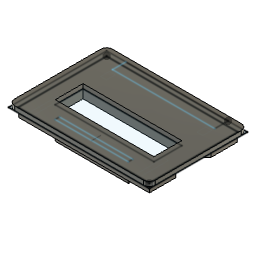
DB19IDC20 v9 (Autodesk Fusion 360 design; units mm, degrees)
Autodesk Fusion 360 part; units mm, degrees
sketch "Sketch1" plane through (0, 0, 0) normal (0, 0, 1) x (1, 0, 0) in component "box"
  line L0 (0, 0) -> (34.9, 0)
  line L1 (34.9, 0) -> (34.9, 31.9)
  line L2 (34.9, 31.9) -> (0, 31.9)
  line L3 (0, 31.9) -> (0, 0)
  line L4 (-5.05, 0) -> (39.95, 0)
  line L5 (39.95, 0) -> (39.95, 31.9)
  line L6 (39.95, 31.9) -> (-5.05, 31.9)
  line L7 (-5.05, 31.9) -> (-5.05, 0)
  line L8 (-6.55, 31.9) -> (-6.55, -1.5)
  line L9 (-6.55, -1.5) -> (41.45, -1.5)
  line L10 (41.45, -1.5) -> (41.45, 31.9)
  line L11 (34.9, 0) -> (36.4, 0)
  line L12 (36.4, 0) -> (36.4, 10)
  line L13 (36.4, 10) -> (34.9, 10)
  line L14 (34.9, 10) -> (34.9, 0)
  line L15 (0, 0) -> (-1.5, 0)
  line L16 (-1.5, 0) -> (-1.5, 10)
  line L17 (-1.5, 10) -> (0, 10)
  line L18 (0, 10) -> (0, 0)
  line L19 (0, 23.3) -> (2, 23.3)
  line L20 (2, 23.3) -> (2, 26.3)
  line L21 (2, 26.3) -> (0, 26.3)
  line L22 (0, 26.3) -> (0, 23.3)
  line L23 (34.9, 23.3) -> (32.9, 23.3)
  line L24 (32.9, 23.3) -> (32.9, 26.3)
  line L25 (32.9, 26.3) -> (34.9, 26.3)
  line L26 (34.9, 26.3) -> (34.9, 23.3)
  line L27 (39.95, 31.9) -> (34.9, 31.9)
  line L28 (34.9, 31.9) -> (34.9, 30.4)
  line L29 (34.9, 30.4) -> (39.95, 30.4)
  line L30 (39.95, 30.4) -> (39.95, 31.9)
  line L31 (-5.05, 31.9) -> (0, 31.9)
  line L32 (0, 31.9) -> (0, 30.4)
  line L33 (0, 30.4) -> (-5.05, 30.4)
  line L34 (-5.05, 30.4) -> (-5.05, 31.9)
  line L35 (-5.05, 31.9) -> (-6.55, 31.9)
  line L36 (41.45, 31.9) -> (39.95, 31.9)
  line L37 (12.45, 7.5) -> (22.45, 7.5)
  line L38 (22.45, 7.5) -> (22.45, 6)
  line L39 (22.45, 6) -> (12.45, 6)
  line L40 (12.45, 6) -> (12.45, 7.5)
  line L41 (17.45, 6) -> (17.45, 0) construction
  line L42 (17.45, 31.9) -> (17.45, -1.5) construction
  dimension "d4" = 34.9
  dimension "d5" = 31.9
  dimension "d6" = 45
  dimension "d7" = 5.05
  dimension "d8" = 1.5
  dimension "d9" = 1.5
  dimension "d10" = 10
  dimension "d11" = 1.5
  dimension "d12" = 10
  dimension "d13" = 2
  dimension "d14" = 3
  dimension "d15" = 23.3
  dimension "d16" = 2
  dimension "d17" = 3
  dimension "d18" = 1.5
  dimension "d19" = 1.5
  dimension "d27" = 10
  dimension "d28" = 1.5
  dimension "d29" = 6
  constraint horizontal L0
  constraint vertical L1
  constraint horizontal L2
  constraint vertical L3
  constraint coincident L0.start L3.end
  constraint horizontal L4
  constraint vertical L5
  constraint horizontal L6
  constraint vertical L7
  constraint horizontal L11
  constraint vertical L12
  constraint horizontal L13
  constraint vertical L14
  constraint horizontal L15
  constraint vertical L16
  constraint horizontal L17
  constraint vertical L18
  constraint horizontal L19
  constraint vertical L20
  constraint horizontal L21
  constraint vertical L22
  constraint coincident L3 L19.start
  constraint horizontal L23
  constraint vertical L24
  constraint horizontal L25
  constraint vertical L26
  constraint coincident L1 L23.start
  constraint collinear L19 L23
  constraint horizontal L27
  constraint vertical L28
  constraint horizontal L29
  constraint vertical L30
  constraint horizontal L31
  constraint vertical L32
  constraint horizontal L33
  constraint vertical L34
  constraint perpendicular L8 L35
  constraint perpendicular L30 L36
  constraint horizontal L37
  constraint vertical L38
  constraint horizontal L39
  constraint vertical L40
  constraint midpoint L39 L41.start
  constraint midpoint L0 L41.end
  constraint perpendicular L39 L41
  constraint midpoint L2 L42.start
  constraint midpoint L9 L42.end
  measures "d4" distance of L0.start L0.end
  measures "d5" distance of L0 L2
  measures "d6" distance of L4.start L4.end
  measures "d7" distance of L3 L7
  measures "d9" distance of L0.end L11.end
  measures "d10" distance of L0.end L13.end
  measures "d11" distance of L0.start L15.end
  measures "d12" distance of L0.start L17.end
  measures "d13" distance of L19.start L19.end
  measures "d14" distance of L19.start L21.end
  measures "d15" distance of L4 L19
  measures "d16" distance of L23.start L23.end
  measures "d17" distance of L23.start L25.end
  measures "d18" distance of L5.end L29.end
  measures "d19" distance of L6.end L33.end
  measures "d27" distance of L37.start L37.end
  measures "d28" distance of L37.start L39.end
  measures "d29" distance of L0 L39
extrude "Extrude1" add sketch "Sketch1" along normal blind 1.5 contours L0 L1 L2 L3 L4 L6 L14 L18 L19 L20 L21 L23 L24 L25 L28 L32 | L3 L4 L7 L16 L17 L22 L33 | L1 L4 L5 L12 L13 L26 L29 | L37 L38 L39 L40 makes body 1 in component "box"
extrude "Extrude2" add sketch "Sketch1" along normal blind 8.8 contours L3 L4 L15 L16 L17 L18 | L1 L4 L11 L12 L13 L14 | L3 L19 L20 L21 L22 | L1 L23 L24 L25 L26 | L3 L6 L7 L31 L32 L33 L34 | L1 L5 L6 L27 L28 L29 L30 bodies 1 in component "box"
extrude "Extrude3" add sketch "Sketch1" along normal blind 13.2 contours L0 L4 L5 L7 L8 L9 L10 L11 L15 L30 L34 L35 L36 bodies 1 in component "box"
extrude "Extrude4" add sketch "Sketch1" along normal blind 5.2 contours L37 L38 L39 L40 bodies 1 in component "box"
fillet "Fillet1" radius 2 1 edges at (41.45, -1.5, 6.6) on bodies 1 in component "box"
fillet "Fillet1" radius 2 1 edges at (-6.55, -1.5, 6.6) on bodies 1 in component "box"
extrude "Extrude5" add 2 faces at (36.5833, 31.4, 8.8) (-3.3667, 30.9, 8.8) along direction (0, 0, 1) up to surface end surface through (0, 0, 13.2) normal (0, 0, 1) offset 0 on bodies 1 bodies 1 in component "box"
fillet "Fillet2" radius 2 2 edges at (41.45, 31.9, 6.6) (-6.55, 31.9, 6.6) on bodies 1 in component "box"
sketch "Sketch1 (2)" plane through (0, 0, 1.5) normal (0, 0, 1) x (-1, 0, 0) in component "cover"
  line L0 (-12.45, -6) -> (-12.45, -7.5)
  line L1 (-12.45, -7.5) -> (-22.45, -7.5)
  line L2 (-22.45, -7.5) -> (-22.45, -6)
  line L3 (-22.45, -6) -> (-12.45, -6)
  line L4 (-32.9, -26.3) -> (-34.9, -26.3)
  line L5 (-34.9, -26.3) -> (-34.9, -23.3)
  line L6 (-34.9, -23.3) -> (-32.9, -23.3)
  line L7 (-32.9, -23.3) -> (-32.9, -26.3)
  line L8 (0, -23.3) -> (0, -26.3)
  line L9 (0, -26.3) -> (-2, -26.3)
  line L10 (-2, -26.3) -> (-2, -23.3)
  line L11 (-2, -23.3) -> (0, -23.3)
  line L12 (-34.9, -31.9) -> (0, -31.9)
  line L13 (0, -31.9) -> (0, -30.4)
  line L14 (0, -30.4) -> (5.05, -30.4)
  line L15 (5.05, -30.4) -> (5.05, 0)
  line L16 (5.05, 0) -> (1.5, 0)
  line L17 (1.5, 0) -> (1.5, -10)
  line L18 (1.5, -10) -> (0, -10)
  line L19 (0, -10) -> (0, 0)
  line L20 (0, 0) -> (-34.9, 0)
  line L21 (-34.9, 0) -> (-34.9, -10)
  line L22 (-34.9, -10) -> (-36.4, -10)
  line L23 (-36.4, -10) -> (-36.4, 0)
  line L24 (-36.4, 0) -> (-39.95, 0)
  line L25 (-39.95, 0) -> (-39.95, -30.4)
  line L26 (-39.95, -30.4) -> (-34.9, -30.4)
  line L27 (-34.9, -30.4) -> (-34.9, -31.9)
  line L28 (-39.95, 0) -> (5.05, 0)
  line L29 (5.05, 0) -> (5.05, -30.4)
  line L30 (5.05, -30.4) -> (-39.95, -30.4)
  line L31 (-39.95, -30.4) -> (-39.95, 0)
  line L32 (-41.45, 1.5) -> (6.55, 1.5)
  line L33 (6.55, 1.5) -> (6.55, -31.9)
  line L34 (6.55, -31.9) -> (-41.45, -31.9)
  line L35 (-41.45, -31.9) -> (-41.45, 1.5)
  line L36 (-0.6, -16.7) -> (-34.3, -16.7)
  line L37 (-34.3, -16.7) -> (-34.3, -7.2)
  line L38 (-34.3, -7.2) -> (-0.6, -7.2)
  line L39 (-0.6, -7.2) -> (-0.6, -16.7)
  line L40 (-39.75, -0.2) -> (4.85, -0.2)
  line L41 (4.85, -0.2) -> (4.85, -30.2)
  line L42 (4.85, -30.2) -> (-39.75, -30.2)
  line L43 (-39.75, -30.2) -> (-39.75, -0.2)
  line L44 (0, -27.3772) -> (-34.9, -27.3772)
  line L45 (-34.9, -27.3772) -> (-34.9, -31.9)
  line L46 (-34.9, -31.9) -> (0, -31.9)
  line L47 (0, -31.9) -> (0, -27.3772)
  line L48 (-29.95, -2.8246) -> (-4.95, -2.8246)
  line L49 (-4.95, -2.8246) -> (-4.95, -4.3246)
  line L50 (-4.95, -4.3246) -> (-29.95, -4.3246)
  line L51 (-29.95, -4.3246) -> (-29.95, -2.8246)
  line L52 (-17.45, -2.8246) -> (-17.45, -7.2) construction
  dimension "d41" = 7.2
  dimension "d42" = 7.15
  dimension "d43" = 7.15
  dimension "d44" = 18.2
  dimension "d45" = 0.2
  dimension "d98" = 1.5
  dimension "d99" = 25
  constraint horizontal L28
  constraint vertical L29
  constraint horizontal L30
  constraint vertical L31
  constraint coincident L14.end L15.start
  constraint coincident L24.end L25.start
  constraint horizontal L36
  constraint vertical L37
  constraint horizontal L38
  constraint vertical L39
  constraint horizontal L44
  constraint vertical L45
  constraint horizontal L46
  constraint vertical L47
  constraint coincident L12.start L27.end
  constraint horizontal L48
  constraint vertical L49
  constraint horizontal L50
  constraint vertical L51
  constraint midpoint L48 L52.start
  constraint midpoint L38 L52.end
  constraint perpendicular L48 L52
  measures "d41" distance of L28 L38
  measures "d42" distance of L33 L39
  measures "d43" distance of L35 L37
  measures "d44" distance of L32 L36
  measures "d98" distance of L48.start L50.end
  measures "d99" distance of L49 L51
extrude "Extrude1'" add sketch "Sketch1 (2)" along normal blind 1.5 separate body contours L0 L2 L3 L38 | L4 L5 L6 L7 | L8 L9 L10 L11 | L12 L13 L27 L30 L34 L45 L46 L47 | L13 L14 L15 L16 L20 L24 L25 L26 L27 L28 L29 L30 L31 L32 L33 L34 L35 L45 L47 | L30 L42 L45 L47 | L23 L24 L25 L26 L28 L30 L31 L40 L42 L43 L45 | L14 L15 L16 L17 L28 L29 L30 L40 L41 L42 L47 | L42 L44 L45 L47 | L17 L18 L19 L21 L22 L23 L40 L41 L42 L43 L44 L45 L47 | L21 L23 L28 L40 | L17 L19 L28 L40 | L21 L22 L23 L40 | L19 L20 L21 L28 L40 | L17 L18 L19 L40 | L48 L49 L50 L51 makes body 2 in component "cover"
extrude "Extrude2'" add sketch "Sketch1 (2)" against normal blind 3 separate body contours L0 L2 L3 L38 | L4 L5 L6 L7 | L8 L9 L10 L11 | L42 L44 L45 L47 | L17 L18 L19 L21 L22 L23 L40 L41 L42 L43 L44 L45 L47 | L21 L22 L23 L40 | L17 L18 L19 L40 | L48 L49 L50 L51 makes body 3 in component "cover"
fillet "Fillet1'" radius 2 4 edges at (41.45, -1.5, 2.25) (41.45, 31.9, 2.25) (-6.55, 31.9, 2.25) (-6.55, -1.5, 2.25) on bodies 2 in component "cover"
sketch "Sketch2" plane through (-6.55, 0, 0) normal (-1, 0, 0) x (0, -1, 0) in component "box"
  line L0 (-29.9, 13.2) -> (-29.9, 0)
  line L1 (-29.9, 0) -> (-0.5, 0)
  line L2 (-0.5, 0) -> (-0.5, 13.2)
  line L3 (-0.5, 13.2) -> (-29.9, 13.2)
  line L4 (-21.2, 13.2) -> (-9.2, 13.2)
  line L5 (-9.2, 13.2) -> (-9.2, 10.2)
  line L6 (-9.2, 10.2) -> (-21.2, 10.2)
  line L7 (-21.2, 10.2) -> (-21.2, 13.2)
  line L8 (-15.2, 10.2) -> (-15.2, 13.2) construction
  dimension "d57" = 12
  dimension "d58" = 3
  constraint horizontal L4
  constraint vertical L5
  constraint horizontal L6
  constraint vertical L7
  constraint coincident L3 L4.start
  constraint midpoint L6 L8.start
  constraint midpoint L3 L8.end
  constraint perpendicular L4 L8
  measures "d57" distance of L4.start L4.end
  measures "d58" distance of L4.start L6.end
ref_plane "WorkPlane1" through (17.45, 15.2, 0) normal (-1, 0, 0) x (0, -1, 0) in component "box"
extrude "Extrude6" add sketch "Sketch2" against normal blind 3 draft -45 from surface at -1.5 contours L3 L4 L5 L6 L7 bodies 1 in component "box"
mirror "Mirror1" about plane through (17.45, 15.2, 0) normal (-1, 0, 0) of "Extrude6" in component "box"
extrude "Extrude6'" cut sketch "Sketch2" against normal blind 3 draft -45 from surface at -1.7 contours L3 L4 L5 L6 L7 sketch seen with x (1, 0, 0) y (0, 1, 0) z (0, 0, 1) at (0, 0, -11.7) bodies 3 in component "cover"
mirror "Mirror2" about plane through (17.45, 15.2, -11.7) normal (-1, 0, 0) of "Extrude6'" in component "cover"
shell "Shell3" thickness 1.5 removed faces 1 at (11.8333, 25.7, -1.5) on bodies 3 in component "cover"
extrude "Extrude7" cut 1 faces at (11.2238, 25.7, 0) along direction (0, 0, 1) blind 1.5 on bodies 3 bodies 3 makes body 4 at (38.5429, 16.7, 1.5) in component "cover"
extrude "Extrude8" cut sketch "Sketch1 (2)" against normal blind 3 contours L30 L42 L45 L47 | L42 L44 L45 L47 bodies 4 in component "cover"
fillet "Fillet3" radius 0.6 1 edges at (39.75, 15.2, -1.5) on bodies 4 in component "cover"
fillet "Fillet4" radius 0.6 1 edges at (-4.85, 15.2, -1.5) on bodies 4 in component "cover"
extrude "Extrude9" add sketch "Sketch1 (2)" against normal blind 1 contours L42 L44 L45 L47 bodies 2 4 in component "cover"
extrude "Extrude10" add sketch "Sketch1 (2)" against normal blind 6.4 contours L48 L49 L50 L51 bodies 2 in component "cover"
component "box" placed x (1, 0, 0) y (0, 1, 0) z (0, 0, 1) at (0, 0, 0)
component "cover" placed x (1, 0, 0) y (0, 1, 0) z (0, 0, 1) at (0, 0, 11.7)
equation "gap = 0.3 mm"
equation "width = 34.60 mm"
equation "length = 31.60 mm"
equation "d4 = width + gap"
equation "d5 = length + gap"
equation "d7 = ( ( 45 - 34.90 ) / 2 ) * 1 mm"
equation "d15 = 23 mm + gap"
equation "ep = 1.5 mm"
equation "d21 = ep"
equation "d23 = ep + 7.3 mm"
equation "d40 = -ep"
equation "d41 = 7.5 mm - gap"
equation "d42 = 7.45 mm - gap"
equation "d43 = 7.45 mm - gap"
equation "d44 = 17.90 mm + gap"
equation "d46 = ep"
equation "d48 = -2 * ep"
equation "d60 = -ep"
equation "d82 = -ep - 0.20 mm"
equation "d90 = -2 * ep"
